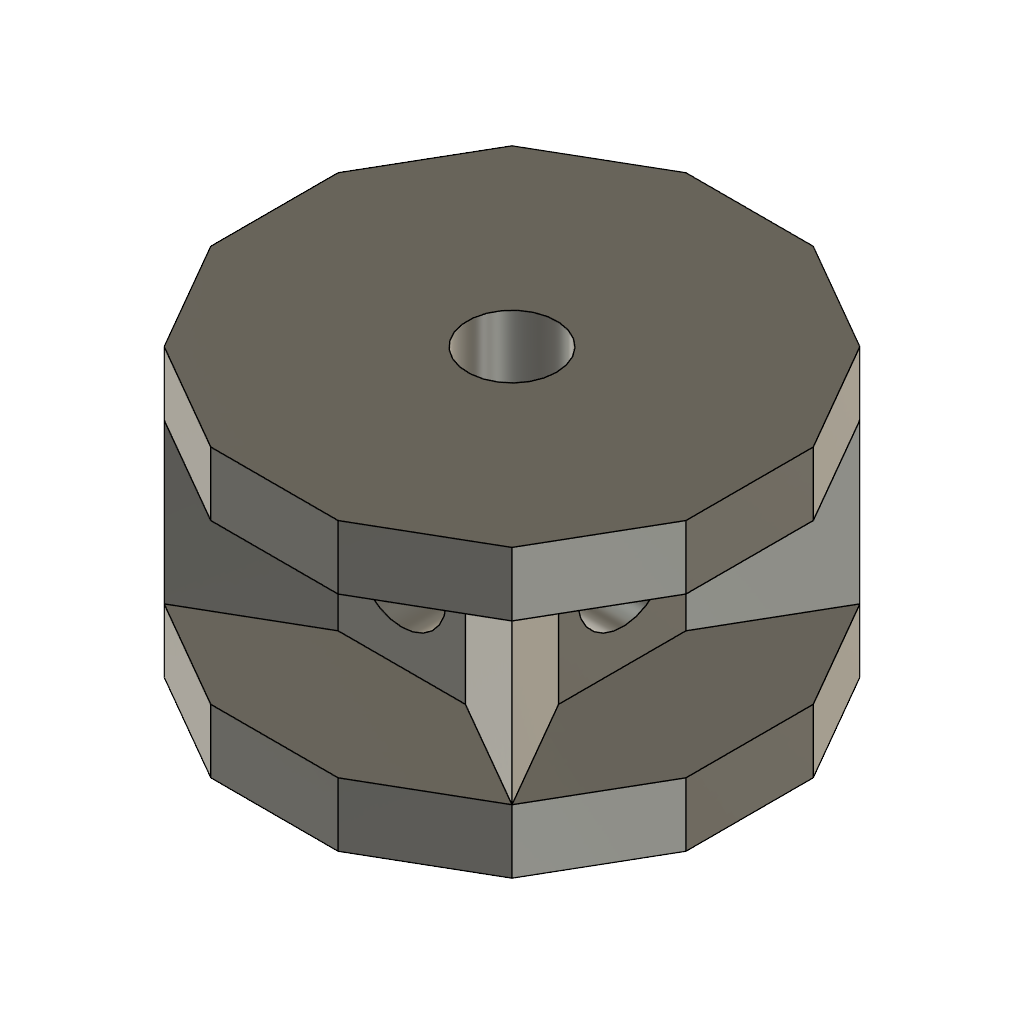
pieza_1 (Autodesk Fusion 360 design; units mm, degrees)
part number: 2026-11-07-23-52-55-872
Autodesk Fusion 360 part; units mm, degrees
sketch "Boceto1" plane through (0, 0, 0) normal (0, 0, 1) x (1, 0, 0)
  line L0 (0, 0) -> (10, -17.3205)
  line L1 (10, -17.3205) -> (27.3205, -27.3205)
  line L2 (27.3205, -27.3205) -> (47.3205, -27.3205)
  line L3 (47.3205, -27.3205) -> (64.641, -17.3205)
  line L4 (64.641, -17.3205) -> (74.641, 0)
  line L5 (74.641, 0) -> (74.641, 20)
  line L6 (74.641, 20) -> (64.641, 37.3205)
  line L7 (64.641, 37.3205) -> (47.3205, 47.3205)
  line L8 (47.3205, 47.3205) -> (27.3205, 47.3205)
  line L9 (27.3205, 47.3205) -> (10, 37.3205)
  line L10 (10, 37.3205) -> (0, 20)
  line L11 (0, 20) -> (0, 0)
  point P0 (37.3205, 10)
  dimension "d1" = 20
  constraint coincident L0.start L11.end
  measures "d1" distance of L0.start L10.end
sketch "Boceto2" plane through (0, 0, 10) normal (0, 0, 1) x (-1, 0, 0)
  line L0 (0, -20) -> (0, 0)
  line L1 (0, 0) -> (-10, 17.3205)
  line L2 (-10, 17.3205) -> (-27.3205, 27.3205)
  line L3 (-27.3205, 27.3205) -> (-47.3205, 27.3205)
  line L4 (-47.3205, 27.3205) -> (-64.641, 17.3205)
  line L5 (-64.641, 17.3205) -> (-74.641, 0)
  line L6 (-74.641, 0) -> (-74.641, -20)
  line L7 (-74.641, -20) -> (-64.641, -37.3205)
  line L8 (-64.641, -37.3205) -> (-47.3205, -47.3205)
  line L9 (-47.3205, -47.3205) -> (-27.3205, -47.3205)
  line L10 (-27.3205, -47.3205) -> (-10, -37.3205)
  line L11 (-10, -37.3205) -> (0, -20)
  line L12 (-27.3205, -27.3205) -> (-47.3205, -27.3205)
  line L13 (-20, -20) -> (-20, 0)
  line L14 (-20, 0) -> (-10, 17.3205)
  line L15 (-20, -20) -> (-10, -37.3205)
  line L16 (-27.3205, -27.3205) -> (-10, -37.3205)
  line L17 (-27.3205, 7.2786) -> (-47.3205, 7.3205)
  line L18 (-27.3205, 7.2786) -> (-10, 17.3205)
  line L19 (-47.3205, 7.3205) -> (-64.641, 17.3205)
  line L20 (-54.641, -20) -> (-54.641, 0)
  line L21 (-54.641, 0) -> (-64.641, 17.3205)
  line L22 (-54.641, -20) -> (-64.641, -37.3205)
  line L23 (-47.3205, -27.3205) -> (-64.641, -37.3205)
  dimension "d4" = 20
  dimension "d5" = 20
  dimension "d6" = 20
  dimension "d7" = 20
  constraint coincident L1.end L2.start
  constraint perpendicular L2 L14
  constraint coincident L10.end L11.start
  constraint perpendicular L10 L15
  constraint coincident L4.end L5.start
  constraint perpendicular L4 L21
  constraint coincident L7.end L8.start
  measures "d4" distance of L9.end L12.start
  measures "d5" distance of L12.start L12.end
  measures "d6" distance of L3.end L17.end
  measures "d7" distance of L6.end L20.start
sketch "Boceto3" plane through (0, 0, 10) normal (0, 0, 1) x (-1, 0, 0)
  line L0 (-74.641, -20) -> (-64.641, -37.3205)
  line L1 (-64.641, -37.3205) -> (-47.3205, -47.3205)
  line L2 (-47.3205, -47.3205) -> (-27.3205, -47.3205)
  line L3 (-27.3205, -47.3205) -> (-10, -37.3205)
  line L4 (-10, -37.3205) -> (0, -20)
  line L5 (0, -20) -> (0, 0)
  line L6 (0, 0) -> (-10, 17.3205)
  line L7 (-10, 17.3205) -> (-27.3205, 27.3205)
  line L8 (-27.3205, 27.3205) -> (-47.3205, 27.3205)
  line L9 (-47.3205, 27.3205) -> (-64.641, 17.3205)
  line L10 (-64.641, 17.3205) -> (-74.641, 0)
  line L11 (-74.641, 0) -> (-74.641, -20)
  line L12 (-20, 0) -> (-20, -20)
  line L13 (-27.3205, 7.3205) -> (-47.3205, 7.3205)
  line L14 (-27.3205, -27.3205) -> (-47.3205, -27.3205)
  line L15 (-47.3205, -27.3205) -> (-64.641, -37.3205)
  line L16 (-54.641, -20) -> (-54.641, 0)
  line L17 (-54.641, 0) -> (-64.641, 17.3205)
  line L18 (-47.3205, 7.3205) -> (-64.641, 17.3205)
  line L19 (-27.3205, 7.3205) -> (-10, 17.3205)
  line L20 (-20, 0) -> (-10, 17.3205)
  line L21 (-20, -20) -> (-10, -37.3205)
  line L22 (-27.3205, -27.3205) -> (-10, -37.3205)
  line L23 (-64.641, -37.3205) -> (-54.641, -20)
  dimension "d10" = 20
  dimension "d11" = 20
  dimension "d12" = 20
  dimension "d13" = 20
  dimension "d14" = 20
  dimension "d15" = 20
  dimension "d16" = 20
  dimension "d17" = 20
  constraint coincident L0.end L1.start
  constraint coincident L9.end L10.start
  constraint coincident L6.end L7.start
  constraint coincident L3.end L4.start
  measures "d10" distance of L5.end L12.start
  measures "d11" distance of L12.start L12.end
  measures "d12" distance of L7.end L13.start
  measures "d13" distance of L13.start L13.end
  measures "d14" distance of L0.start L16.start
  measures "d15" distance of L2.end L14.start
  measures "d16" distance of L14.start L14.end
  measures "d17" distance of L16.start L16.end
sketch "Boceto4" plane through (0, 0, 40) normal (0, 0, 1) x (-1, 0, 0)
  circle A0 centre (-37.3205, -10) radius 3
  line L0 (-74.641, -20) -> (-64.641, -37.3205)
  line L1 (-64.641, -37.3205) -> (-47.3205, -47.3205)
  line L2 (-47.3205, -47.3205) -> (-27.3205, -47.3205)
  line L3 (-27.3205, -47.3205) -> (-10, -37.3205)
  line L4 (-10, -37.3205) -> (0, -20)
  line L5 (0, -20) -> (0, 0)
  line L6 (0, 0) -> (-10, 17.3205)
  line L7 (-10, 17.3205) -> (-27.3205, 27.3205)
  line L8 (-27.3205, 27.3205) -> (-47.3205, 27.3205)
  line L9 (-47.3205, 27.3205) -> (-64.641, 17.3205)
  line L10 (-64.641, 17.3205) -> (-74.641, 0)
  line L11 (-74.641, 0) -> (-74.641, -20)
  line L12 (30, 0) -> (30, -10)
  line L13 (30, -10) -> (35, -18.6603)
  line L14 (35, -18.6603) -> (43.6603, -23.6603)
  line L15 (43.6603, -23.6603) -> (53.6603, -23.6603)
  line L16 (53.6603, -23.6603) -> (62.3205, -18.6603)
  line L17 (62.3205, -18.6603) -> (67.3205, -10)
  line L18 (67.3205, -10) -> (67.3205, 0)
  line L19 (67.3205, 0) -> (62.3205, 8.6603)
  line L20 (62.3205, 8.6603) -> (53.6603, 13.6603)
  line L21 (53.6603, 13.6603) -> (43.6603, 13.6603)
  line L22 (43.6603, 13.6603) -> (35, 8.6603)
  line L23 (35, 8.6603) -> (30, 0)
  point P0 (48.6603, -5)
  dimension "d61" = 10
  measures "d61" distance of L12.start L12.end
extrude "Extruir4" add sketch "Boceto4" against normal blind 5 contours L12 L13 L14 L15 L16 L17 L18 L19 L20 L21 L22 L23 makes body 1
copy_body "CopiarPegarCuerpos2" bodies 1 makes body 2
move_body "Desplazar2" bodies 2 to x (1, 0, 0) y (0, 1, 0) z (0, 0, 1) at (0, 0, -17.5)
sketch "Boceto5" plane through (0, 0, 22.5) normal (0, 0, 1) x (-1, 0, 0)
  line L0 (35, 8.6603) -> (30, 0)
  line L1 (30, 0) -> (30, -10)
  line L2 (30, -10) -> (35, -18.6603)
  line L3 (35, -18.6603) -> (43.6603, -23.6603)
  line L4 (43.6603, -23.6603) -> (53.6603, -23.6603)
  line L5 (53.6603, -23.6603) -> (62.3205, -18.6603)
  line L6 (62.3205, -18.6603) -> (67.3205, -10)
  line L7 (67.3205, -10) -> (67.3205, 0)
  line L8 (67.3205, 0) -> (62.3205, 8.6603)
  line L9 (62.3205, 8.6603) -> (53.6603, 13.6603)
  line L10 (53.6603, 13.6603) -> (43.6603, 13.6603)
  line L11 (43.6603, 13.6603) -> (35, 8.6603)
  line L12 (53.6603, -13.6603) -> (43.6603, -13.6603)
  line L13 (43.6603, -13.6603) -> (35, -18.6603)
  line L14 (57.3205, -10) -> (57.3205, 0)
  line L15 (57.3205, 0) -> (62.3205, 8.6603)
  line L16 (53.6603, 3.6603) -> (43.6603, 3.6603)
  line L17 (43.6603, 3.6603) -> (35, 8.6603)
  line L18 (40, 0) -> (40, -10)
  line L19 (40, -10) -> (35, -18.6603)
  line L20 (53.6603, -13.6603) -> (62.3205, -18.6603)
  line L21 (57.3205, -10) -> (62.3205, -18.6603)
  line L22 (62.3205, 8.6603) -> (53.6603, 3.6603)
  line L23 (40, 0) -> (35, 8.6603)
  dimension "d67" = 10
  dimension "d68" = 10
  dimension "d69" = 10
  dimension "d70" = 10
  dimension "d71" = 10
  dimension "d72" = 10
  dimension "d73" = 10
  dimension "d74" = 10
  constraint coincident L2.end L3.start
  constraint perpendicular L12 L14
  constraint coincident L8.end L9.start
  constraint coincident L0.start L11.end
  constraint coincident L5.end L6.start
  constraint perpendicular L11 L23
  measures "d67" distance of L4.end L12.start
  measures "d68" distance of L12.start L12.end
  measures "d69" distance of L6.end L14.start
  measures "d70" distance of L14.start L14.end
  measures "d71" distance of L9.end L16.start
  measures "d72" distance of L16.start L16.end
  measures "d73" distance of L0.end L18.start
  measures "d74" distance of L18.start L18.end
extrude "Extruir5" add sketch "Boceto5" along normal blind 12.5 contours L12 L13 L14 L15 L16 L17 L18 L19 L20 L21 L22 L23 bodies 1 2
hole "Agujero13" at (-48.6603, -3.6603, 28.75) direction (0, 1, 0) diameter 7 depth 6 tip angle 180 bodies 1
hole "Agujero14" at (-57.3205, 5, 28.75) direction (1, 0, 0) diameter 7 depth 6 tip angle 180 bodies 1
hole "Agujero15" at (-48.6603, 13.6603, 28.75) direction (0, -1, 0) diameter 7 depth 6 tip angle 180 bodies 1
hole "Agujero16" at (-40, 5, 28.75) direction (-1, 0, 0) diameter 7 depth 6 tip angle 180 bodies 1
hole "Agujero17" at (-48.6603, 5, 17.5) direction (0, 0, 1) diameter 7 depth 8 tip angle 180 bodies 1
hole "Agujero18" at (-48.6603, 5, 40) direction (0, 0, -1) diameter 7 depth 8 tip angle 180 bodies 1
